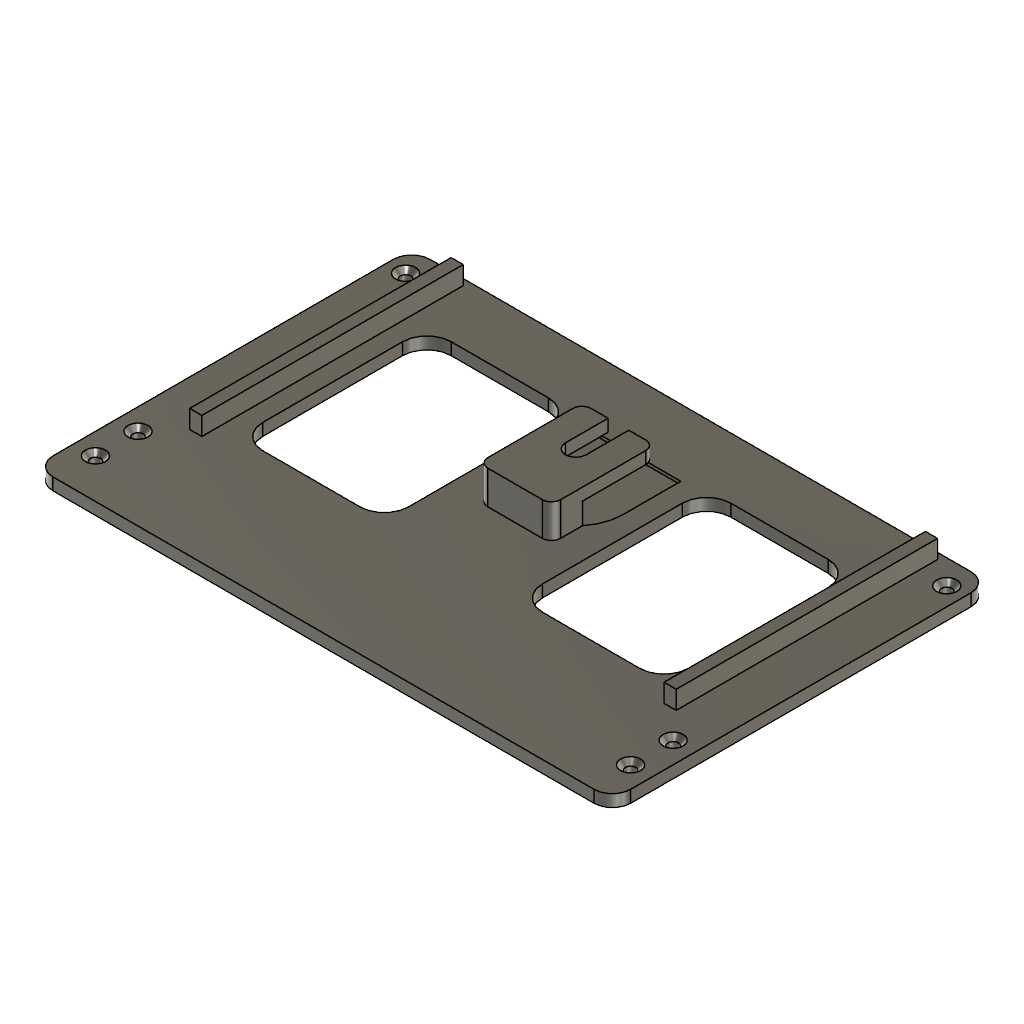
DSLR_Platform (Autodesk Fusion 360 design; units mm, degrees)
part number: 2026-10-19-10-28-43-407
Autodesk Fusion 360 part; units mm, degrees
sketch "Sketch1" plane through (0, 0, 0) normal (0, 0, 1) x (1, 0, 0)
  line L0 (-89, 42) -> (89, 42)
  arc A0 (89, 42) -> (95, 48) centre (89, 48) ccw
  line L1 (95, 48) -> (95, 160)
  arc A1 (95, 160) -> (89, 166) centre (89, 160) ccw
  line L2 (89, 166) -> (-89, 166)
  arc A2 (-89, 166) -> (-95, 160) centre (-89, 160) ccw
  line L3 (-95, 160) -> (-95, 48)
  arc A3 (-95, 48) -> (-89, 42) centre (-89, 48) ccw
extrude "platform_plate" add sketch "Sketch1" along normal blind 4 from surface at 171
sketch "platform_rib" plane through (0, 0, 0) normal (0, 0, 1) x (1, 0, 0)
  line L0 (76, 78) -> (80, 78)
  line L1 (80, 78) -> (80, 164)
  line L2 (80, 164) -> (76, 164)
  line L3 (76, 164) -> (76, 78)
extrude "platform_rib (1)" add sketch "platform_rib" along normal blind 6.01 from surface at 174.99
sketch "platform_rib (1)" plane through (0, 0, 0) normal (0, 0, 1) x (1, 0, 0)
  line L0 (-80, 78) -> (-76, 78)
  line L1 (-76, 78) -> (-76, 164)
  line L2 (-76, 164) -> (-80, 164)
  line L3 (-80, 164) -> (-80, 78)
extrude "platform_rib (2)" add sketch "platform_rib (1)" along normal blind 6.01 from surface at 174.99
sketch "pedestal" plane through (0, 0, 0) normal (0, 0, 1) x (1, 0, 0)
  line L0 (-9, 105) -> (9, 105)
  arc A0 (9, 105) -> (12, 108) centre (9, 108) ccw
  line L1 (12, 108) -> (12, 136)
  arc A1 (12, 136) -> (9, 139) centre (9, 136) ccw
  line L2 (9, 139) -> (-9, 139)
  arc A2 (-9, 139) -> (-12, 136) centre (-9, 136) ccw
  line L3 (-12, 136) -> (-12, 108)
  arc A3 (-12, 108) -> (-9, 105) centre (-9, 108) ccw
extrude "pedestal (1)" add sketch "pedestal" along normal blind 11.01 from surface at 174.99
sketch "windows" plane through (0, 0, 0) normal (0, 0, 1) x (1, 0, 0)
  line L0 (-62, 84) -> (-30, 84)
  arc A0 (-30, 84) -> (-22, 92) centre (-30, 92) ccw
  line L1 (-22, 92) -> (-22, 138)
  arc A1 (-22, 138) -> (-30, 146) centre (-30, 138) ccw
  line L2 (-30, 146) -> (-62, 146)
  arc A2 (-62, 146) -> (-70, 138) centre (-62, 138) ccw
  line L3 (-70, 138) -> (-70, 92)
  arc A3 (-70, 92) -> (-62, 84) centre (-62, 92) ccw
  line L4 (30, 84) -> (62, 84)
  arc A4 (62, 84) -> (70, 92) centre (62, 92) ccw
  line L5 (70, 92) -> (70, 138)
  arc A5 (70, 138) -> (62, 146) centre (62, 138) ccw
  line L6 (62, 146) -> (30, 146)
  arc A6 (30, 146) -> (22, 138) centre (30, 138) ccw
  line L7 (22, 138) -> (22, 92)
  arc A7 (22, 92) -> (30, 84) centre (30, 92) ccw
extrude "windows (1)" cut sketch "windows" along normal blind 5 from surface at 170.5
sketch "tower_screws_hole" plane through (0, 0, 0) normal (0, 0, 1) x (1, 0, 0)
  circle A0 centre (-88, 55) radius 1.7
  circle A1 centre (88, 55) radius 1.7
  circle A2 centre (-88, 69) radius 1.7
  circle A3 centre (88, 69) radius 1.7
extrude "tower_screws_hole (1)" cut sketch "tower_screws_hole" against normal blind 5 from surface at 175.5
sketch "tower_screws_cone" plane through (0, 0, 0) normal (0, 0, 1) x (1, 0, 0)
  circle A0 centre (-88, 55) radius 3.8
  circle A1 centre (88, 55) radius 3.8
  circle A2 centre (-88, 69) radius 3.8
  circle A3 centre (88, 69) radius 3.8
extrude "tower_screws_cone (1)" cut sketch "tower_screws_cone" against normal blind 2.1 draft -45 from surface at 175.5
sketch "leg_screws_hole" plane through (0, 0, 0) normal (0, 0, 1) x (1, 0, 0)
  circle A0 centre (89, 158) radius 1.7
  circle A1 centre (-89, 158) radius 1.7
extrude "leg_screws_hole (1)" cut sketch "leg_screws_hole" against normal blind 5 from surface at 175.5
sketch "leg_screws_cone" plane through (0, 0, 0) normal (0, 0, 1) x (1, 0, 0)
  circle A0 centre (89, 158) radius 3.8
  circle A1 centre (-89, 158) radius 3.8
extrude "leg_screws_cone (1)" cut sketch "leg_screws_cone" against normal blind 2.1 draft -45 from surface at 175.5
sketch "wheel_cavity" plane through (0, 0, 0) normal (0, 0, 1) x (1, 0, 0)
  circle A0 centre (0, 125) radius 15.5
extrude "wheel_cavity (1)" cut sketch "wheel_cavity" along normal blind 8 from surface at 174
sketch "wheel_slot_back" plane through (0, 0, 0) normal (0, 0, 1) x (1, 0, 0)
  line L0 (-15.5, 125) -> (15.5, 125)
  line L1 (15.5, 125) -> (15.5, 144)
  line L2 (15.5, 144) -> (-15.5, 144)
  line L3 (-15.5, 144) -> (-15.5, 125)
extrude "wheel_slot_back (1)" cut sketch "wheel_slot_back" along normal blind 8 from surface at 174
sketch "bolt_slot" plane through (0, 0, 0) normal (0, 0, 1) x (1, 0, 0)
  line L0 (-0.01, 121.6) -> (0.01, 121.6)
  arc A0 (0.01, 121.6) -> (3.4, 124.99) centre (0.01, 124.99) ccw
  line L1 (3.4, 124.99) -> (3.4, 140.61)
  arc A1 (3.4, 140.61) -> (0.01, 144) centre (0.01, 140.61) ccw
  line L2 (0.01, 144) -> (-0.01, 144)
  arc A2 (-0.01, 144) -> (-3.4, 140.61) centre (-0.01, 140.61) ccw
  line L3 (-3.4, 140.61) -> (-3.4, 124.99)
  arc A3 (-3.4, 124.99) -> (-0.01, 121.6) centre (-0.01, 124.99) ccw
extrude "bolt_slot (1)" cut sketch "bolt_slot" along normal blind 5 from surface at 181.5
equation "d1072 = -( 5.00 mm )"
equation "d1075 = -( 2.10 mm )"
equation "d1078 = -( 5.00 mm )"
equation "d1081 = -( 2.10 mm )"
named bodies: "DSLR Platform"
